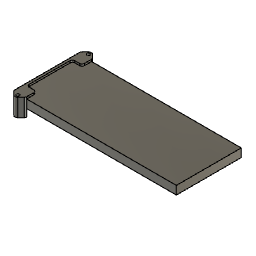
Aquarium Light Holder v4 (Autodesk Fusion 360 design; units mm, degrees)
Autodesk Fusion 360 part; units mm, degrees
sketch "Sketch1" plane through (0, 0, 0) normal (0, 0, 1) x (1, 0, 0) in component "Light"
  line L0 (0, 0) -> (200, 0)
  line L1 (200, 0) -> (200, 81.5)
  line L2 (200, 81.5) -> (0, 81.5)
  line L3 (0, 81.5) -> (0, 0)
  dimension "d1" = 200
  dimension "d2" = 81.5
  constraint horizontal L0
  constraint vertical L1
  constraint horizontal L2
  constraint vertical L3
  constraint coincident L0.start L3.end
  measures "d1" distance of L0.start L0.end
  measures "d2" distance of L0.start L2.end
extrude "Extrude1" add sketch "Sketch1" along normal blind 10.5 makes body 1 in component "Light"
sketch "Sketch1 (2)" plane through (0, 0, 10.5) normal (0, 0, 1) x (-1, 0, 0) in component "Bracket Left"
  line L0 (0, -81.5) -> (0, 0)
  line L1 (0, 0) -> (-200, 0)
  line L2 (-200, 0) -> (-200, -81.5)
  line L3 (-200, -81.5) -> (0, -81.5)
  line L4 (0, -81.5) -> (50, -81.5) construction
  line L5 (0, -81.5) -> (0, -131.5) construction
  line L6 (0, -40.75) -> (50, -40.75) construction
  line L7 (0, 0) -> (50, 0) construction
  line L8 (3, -81.5) -> (3, 0) construction
  line L9 (0, -81.5) -> (-12, -81.5) construction
  line L10 (-12, -81.5) -> (-12, -69.5) construction
  line L11 (-12, -69.5) -> (0, -69.5) construction
  line L12 (0, -69.5) -> (0, -81.5) construction
  line L13 (0, -81.5) -> (-12, -81.5) construction
  line L14 (-12, -81.5) -> (-12, -84.5) construction
  line L15 (-12, -84.5) -> (0, -84.5) construction
  line L16 (0, -84.5) -> (0, -81.5) construction
  line L17 (0, -69.5) -> (3, -69.5) construction
  line L18 (3, -81.5) -> (3, -76.5) construction
  circle A0 centre (-3, -66.5) radius 3 construction
  circle A1 centre (-9, -81.5) radius 3 construction
  line L19 (-9, -81.5) -> (-12, -81.5) construction
  arc A2 (-12, -81.5) -> (-9.0302, -84.4998) centre (-9, -81.5) ccw
  circle A3 centre (-9, -72.5) radius 3 construction
  line L20 (-12, -81.5) -> (-12, -72.5)
  line L21 (-9, -72.5) -> (-9, -69.5) construction
  arc A4 (-9, -69.5) -> (-12, -72.5) centre (-9, -72.5) ccw
  line L22 (-3, -66.5) -> (-3, -69.5) construction
  line L23 (-3, -66.5) -> (0, -66.5) construction
  line L24 (-9, -69.5) -> (-3, -69.5)
  arc A5 (-3, -69.5) -> (0, -66.5) centre (-3, -66.5) ccw
  line L25 (0, -66.5) -> (0, -40.75)
  line L26 (-12, 0) -> (-12, -9)
  arc A6 (-12, -9) -> (-9, -12) centre (-9, -9) ccw
  line L27 (-9, -12) -> (-3, -12)
  arc A7 (0, -15) -> (-3, -12) centre (-3, -15) ccw
  line L28 (0, -15) -> (0, -40.75)
  line L29 (-9, -12) -> (6.7411, -12) construction
  line L30 (3, -12) -> (0, -12)
  line L31 (3, -69.5) -> (0, -69.5)
  circle A8 centre (0, -81.5) radius 3 construction
  arc A9 (0, -84.5) -> (3, -81.5) centre (0, -81.5) ccw
  line L32 (3, -81.5) -> (3, -69.5)
  line L33 (3, -40.75) -> (3, -81.5)
  line L34 (0, -84.5) -> (-9.0302, -84.4998) construction
  line L35 (3, -40.75) -> (3, 0)
  line L36 (-4.5151, -84.4999) -> (-4.5153, -94.4999) construction
  line L37 (-1.2935, -85.1) -> (-8.8884, -85.1) construction
  circle A10 centre (-4.5151, -85.1) radius 3.6 construction
  circle A11 centre (-4.5151, -85.1) radius 2
  arc A12 (-8.0648, -84.5) -> (-0.9655, -84.5) centre (-4.5151, -85.1) ccw
  line L38 (2.1039, -83.6386) -> (-1.9905, -87.6664)
  line L39 (-11.1118, -83.6308) -> (-7.0492, -87.657)
  arc A13 (-0.9655, 3) -> (-8.0648, 3) centre (-4.5151, 3.6) ccw
  line L40 (-11.1118, 2.1308) -> (-7.0492, 6.157)
  arc A14 (-9.0302, 2.9998) -> (-12, 0) centre (-9, 0) ccw
  arc A15 (3, 0) -> (0, 3) centre (0, 0) ccw
  line L41 (2.1039, 2.1386) -> (-1.9905, 6.1664)
  circle A16 centre (-4.5151, 3.6) radius 2
  line L42 (3, -81.5) -> (-12, -81.5)
  line L43 (3, 0) -> (-12, 0)
  dimension "d6" = 50
  dimension "d7" = 50
  dimension "d10" = 50
  dimension "d11" = 50
  dimension "d12" = 3
  dimension "d13" = 12
  dimension "d14" = 12
  dimension "d15" = 12
  dimension "d16" = 3
  dimension "d17" = 5
  dimension "d19" = 3
  dimension "d20" = 3
  dimension "d21" = 3
  dimension "d34" = 10
  dimension "d35" = 0.6
  dimension "d36" = 7.2
  dimension "d37" = 4
  constraint coincident L0.start L3.end
  constraint perpendicular L0 L4
  constraint perpendicular L3 L5
  constraint midpoint L0 L6.start
  constraint perpendicular L0 L6
  constraint coincident L0.end L1.start
  constraint perpendicular L0 L7
  constraint coincident L4 L8.start
  constraint coincident L7 L8.end
  constraint perpendicular L7 L8
  constraint horizontal L9
  constraint vertical L10
  constraint horizontal L11
  constraint vertical L12
  constraint horizontal L13
  constraint vertical L14
  constraint horizontal L15
  constraint vertical L16
  constraint coincident L8 L17.end
  constraint perpendicular L8 L17
  constraint perpendicular L4 L18
  constraint tangent L11 A0
  constraint tangent L0 A0
  constraint tangent L14 A1
  constraint tangent L15 A1
  constraint coincident A1 A2.end
  constraint coincident A1.centre L19.start
  constraint coincident L10 L9.end
  constraint coincident A1 L9.end
  constraint perpendicular L10 L19
  constraint tangent L11 A3
  constraint tangent L10 A3
  constraint coincident A3 L20.end
  constraint tangent A3 L20
  constraint coincident A3.centre L21.start
  constraint coincident L11 L21.end
  constraint coincident A3 L21.end
  constraint perpendicular L11 L21
  constraint tangent L11 A4
  constraint coincident A0.centre L22.start
  constraint coincident L11 L22.end
  constraint coincident A0 L22.end
  constraint perpendicular L11 L22
  constraint coincident A0 L23.end
  constraint perpendicular L0 L23
  constraint tangent L0 A5
  constraint symmetric L25.end L6 L28.end
  constraint symmetric L6 L9.end L26.start
  constraint symmetric L6 L20.end L26.end
  constraint symmetric L6 L21.end A6.end
  constraint symmetric L6 A4 A6
  constraint symmetric L6 L22.end L27.end
  constraint symmetric L6 L23.end A7.start
  constraint symmetric L6 A5 A7
  constraint tangent A6 L29
  constraint coincident L29 L30.start
  constraint coincident L29 L30.end
  constraint coincident L0 L30.end
  constraint symmetric L6 L30.start L17.end
  constraint symmetric L6 L30.end L11.end
  constraint concentric A1 A2
  constraint coincident L15.end A8
  constraint tangent L18 A9
  constraint midpoint L8 L33.start
  constraint symmetric L6 L8.start L8.end
  constraint symmetric L6 L33.start L35.start
  constraint midpoint L34 L36.start
  constraint perpendicular L34 L36
  constraint horizontal L37
  constraint coincident L37 A10.centre
  constraint coincident L36 A10.centre
  constraint concentric A10 A11
  constraint coincident L15 A12.start
  constraint coincident A10 A12.start
  constraint coincident L15 A12.end
  constraint coincident A10 A12.end
  constraint coincident A9 L38.start
  constraint coincident A10 L38.end
  constraint coincident A12 L38.end
  constraint tangent A9 L38
  constraint tangent A12 L38
  constraint coincident A1 L39.start
  constraint coincident A10 L39.end
  constraint tangent A1 L39
  constraint tangent A12 L39
  constraint symmetric L6 L15.end A15.end
  constraint symmetric L6 A2.end A14.start
  constraint symmetric L6 A2 A14
  constraint symmetric L6 A9 A15
  constraint symmetric L6 A12.end A13.start
  constraint symmetric L6 A12.start A13.end
  constraint symmetric L6 A12 A13
  constraint symmetric L6 L38.start L41.start
  constraint symmetric L6 L38.end L41.end
  constraint symmetric L6 L39.start L40.start
  constraint symmetric L6 L39.end L40.end
  constraint symmetric L6 A11 A16
  measures "d6" distance of L0.start L4.end
  measures "d7" distance of L0.start L5.end
  measures "d10" distance of L6.start L6.end
  measures "d11" distance of L0.end L7.end
  measures "d12" distance of L0 L8
  measures "d13" distance of L0.start L9.end
  measures "d14" distance of L0.start L11.end
  measures "d15" distance of L0.start L9.end
  measures "d16" distance of L0.start L15.end
  measures "d17" distance of L8.start L18.end
  measures "d19" radius of A0
  measures "d20" radius of A1
  measures "d21" radius of A3
  measures "d34" distance of L36.start L36.end
  measures "d35" distance of L15 L37
  measures "d36" diameter of A10
  measures "d37" diameter of A11
extrude "Extrude1'" add sketch "Sketch1 (2)" along normal blind 2.4 separate body contours L0 L3 L20 A4 L24 A5 L42 | L3 A2 A9 A12 L38 L39 L42 | L0 L31 L32 L33 L42 | L0 L25 L28 L30 L31 L33 L35 | L0 L1 L26 A6 L27 A7 L43 | L0 L30 L35 L43 | L1 A13 L40 A14 A15 L41 L43 makes body 2 in component "Bracket Left"
extrude "Extrude2" add sketch "Sketch1 (2)" against normal blind 7 contours L3 A2 A9 A12 L38 L39 L42 | L0 L31 L32 L33 L42 | L0 L30 L35 L43 | L1 A13 L40 A14 A15 L41 L43 bodies 2 in component "Bracket Left"
extrude "Extrude3" add sketch "Sketch1 (2)" against normal blind 15.2 contours L3 A2 A9 A12 L38 L39 L42 bodies 2 in component "Bracket Left"
extrude "Extrude4" add sketch "Sketch1 (2)" against normal blind 19.8 contours L1 A13 L40 A14 A15 L41 L43 bodies 2 in component "Bracket Left"
sketch "Sketch2" plane through (0, 0, 0) normal (-1, 0, 0) x (0, -1, 0) in component "Bracket Left"
  line L0 (-81.5, 0) -> (0, 0)
  line L1 (0, 0) -> (0, 10.5)
  line L2 (0, 10.5) -> (-81.5, 10.5)
  line L3 (-81.5, 10.5) -> (-81.5, 0)
  line L4 (-81.5, -4.7) -> (-166.5, -4.7)
  line L5 (-166.5, -4.7) -> (-166.5, 2.6)
  line L6 (-166.5, 2.6) -> (-81.5, -4.7)
  line L7 (-81.5, 3.5) -> (-81.5, 12.9)
  line L8 (-81.5, 12.9) -> (-83.6386, 12.9)
  line L9 (-83.6386, 12.9) -> (-83.6386, -4.7)
  line L10 (-83.6386, -4.7) -> (-81.5, -4.7)
  line L11 (-81.5, -4.7) -> (-81.5, 3.5)
  dimension "d30" = 85
  dimension "d31" = 7.3
  constraint perpendicular L4 L5
  constraint coincident L4.start L6.end
  constraint coincident L4 L9.end
  measures "d30" distance of L4.start L4.end
  measures "d31" distance of L4.end L5.end
extrude "Extrude5" cut sketch "Sketch2" along normal blind 12 and the other way blind 20 contours L4 L6 L9 L10 | L4 L5 L6 L9 bodies 2 in component "Bracket Left"
component "Light" placed x (1, 0, 0) y (0, 1, 0) z (0, 0, 1) at (0, 0, 0)
component "Bracket Left" placed x (1, 0, 0) y (0, 1, 0) z (0, 0, 1) at (0, 0, 0)
equation "d16 = d12"
equation "d19 = d16"
equation "d20 = d16"
equation "d21 = d16"
equation "d35 = ( 4 mm + 1.6 mm + 1.6 mm ) / 2 - d16"
equation "d36 = 4 mm + ( 1.6 * 2 ) * 1 mm"
